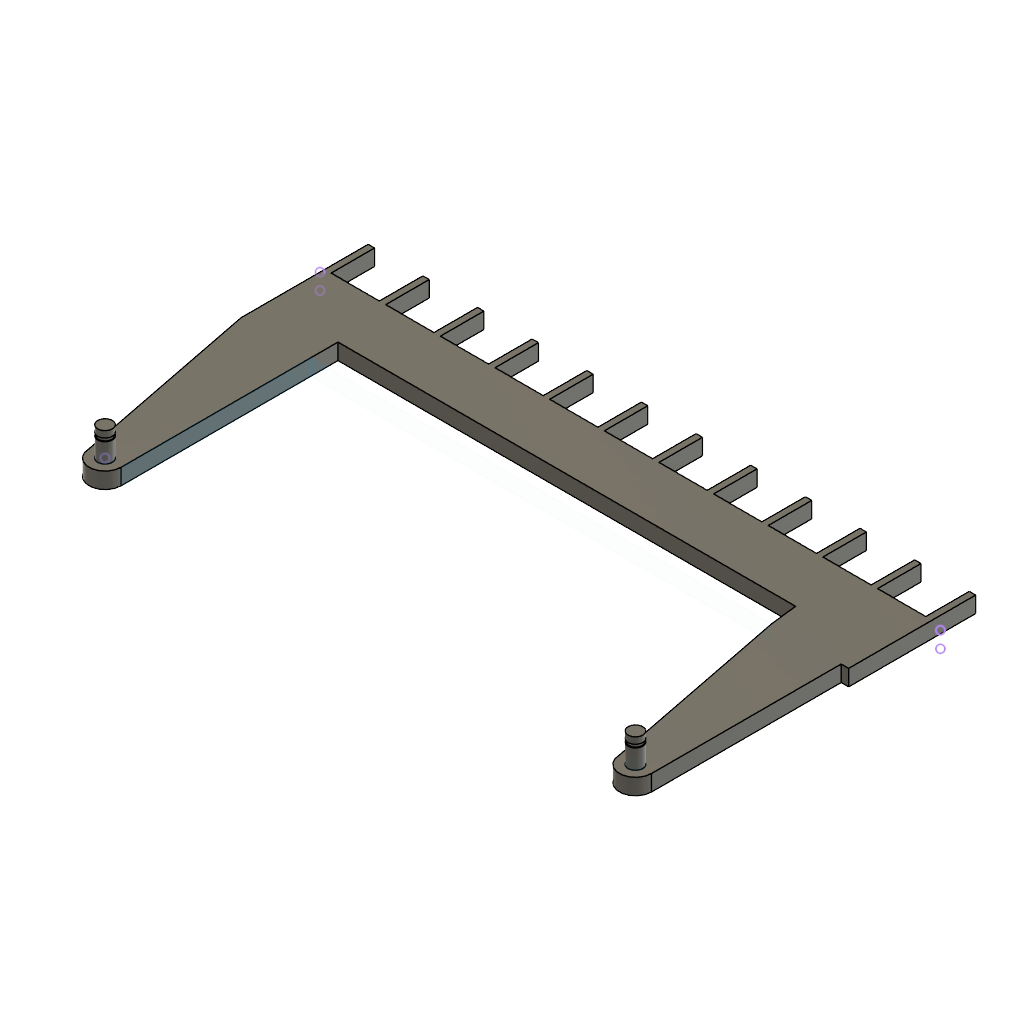
link 8 (Autodesk Fusion 360 design; units mm, degrees)
part number: 2026-11-18-20-14-19-061
Autodesk Fusion 360 part; units mm, degrees
note: some values were not read from the file. Set by a fixed rule: which face or edge a step refers to.
sketch "Sketch1" plane through (0, 0, 0) normal (0, 1, 0) x (1, 0, 0)
  line L0 (0, -5) -> (165, -5)
  arc A0 (165, -5) -> (165, 5) centre (165, 0) ccw
  line L1 (165, 5) -> (0, 5)
  arc A1 (0, 5) -> (0, -5) centre (0, 0) ccw
  line L2 (0, 0) -> (165, 0) construction
  circle A2 centre (0, 0) radius 2.5
  circle A3 centre (165, 0) radius 2.5
  circle A4 centre (0, 0) radius 5
  circle A5 centre (165, 0) radius 5
  line L3 (-16.6629, 74) -> (183.3371, 74)
  line L4 (183.3371, 74) -> (183.3371, 59)
  line L5 (183.3371, 59) -> (-16.6629, 59)
  line L6 (-16.6629, 59) -> (-16.6629, 74)
  line L7 (5, 0) -> (5, 59)
  line L8 (170, 0) -> (170, 59)
  line L9 (-5, 0) -> (-16.6629, 59)
  line L10 (160, 0) -> (148.3371, 59)
  dimension "d1" = 10
  dimension "d2" = 5
  dimension "d3" = 5
  dimension "d4" = 10
  dimension "d5" = 10
  dimension "d6" = 200
  dimension "d7" = 15
  constraint tangent L0 A0
  constraint tangent A0 L1
  constraint parallel L0 L1
  constraint tangent L1 A1
  constraint tangent L0 A1
  constraint horizontal L2
  constraint coincident A1.centre L2.start
  constraint concentric A1 A2
  constraint concentric A0 A3
  constraint concentric A0 A5
  constraint horizontal L3
  constraint vertical L4
  constraint horizontal L5
  constraint vertical L6
  constraint coincident A4 L7.start
  constraint coincident L2 L7.start
  constraint coincident L5 L7.end
  constraint perpendicular L5 L7
  constraint midpoint A0 L8.start
  constraint coincident L5 L8.end
  constraint tangent A5 L8
  constraint perpendicular L5 L8
  constraint midpoint A1 L9.start
  constraint coincident L2 L10.start
  constraint coincident A5 L10.start
  constraint coincident L5 L10.end
  constraint parallel L9 L10
  measures "d1" diameter of A0
  measures "d2" diameter of A2
  measures "d3" diameter of A3
  measures "d4" diameter of A4
  measures "d5" diameter of A5
  measures "d6" distance of L4.end L5.end
  measures "d7" distance of L3.start L5.end
extrude "Extrude1" add sketch "Sketch1" along normal blind 5 contours A1 A4 | A0 A5 | L1 A1 A4 L5 L7 L9 | L1 A4 L7 | A0 L1 A5 L5 L8 L10 | L1 A5 L10 | L3 L4 L5 L6 makes body 1
sketch "Sketch2" plane through (0, 0, 0) normal (0, -1, 0) x (1, 0, 0)
  circle A0 centre (165, 0) radius 2.5
  circle A1 centre (0, 0) radius 2.5
  arc A2 (170, 0) -> (160, 0) centre (165, 0) ccw
  line L0 (160, 0) -> (148.3371, -59)
  line L1 (148.3371, -59) -> (5, -59)
  line L2 (5, -59) -> (5, 0)
  arc A3 (5, 0) -> (-5, 0) centre (0, 0) ccw
  line L3 (-5, 0) -> (-16.6629, -59)
  line L4 (-16.6629, -59) -> (-16.6629, -74)
  line L5 (-16.6629, -74) -> (183.3371, -74)
  line L6 (183.3371, -74) -> (183.3371, -59)
  line L7 (183.3371, -59) -> (170, -59)
  line L8 (170, -59) -> (170, 0)
  circle A4 centre (0, 0) radius 2.5
  dimension "d85" = 15
  constraint concentric A1 A4
  measures "d85" distance of L1 L5
extrude "Extrude2" add sketch "Sketch2" against normal blind 13 contours A1 A4 bodies 1
sketch "Sketch3" plane through (5, 0, 0) normal (1, 0, 0) x (0, 0, -1)
  line L0 (0, 0) -> (59, 0)
  line L1 (59, 0) -> (59, 5)
  line L2 (59, 5) -> (0, 5)
  line L3 (0, 5) -> (0, 0)
sketch "Sketch4" plane through (5, 0, 0) normal (1, 0, 0) x (0, 0, -1)
extrude "Extrude3" cut 1 faces at (-0.7508, 13, 0.3616) along direction (0, -1, 0) blind 3 on bodies 1 bodies 1
sketch "Sketch5" plane through (0, 10, 0) normal (0, 1, 0) x (-1, 0, 0)
  circle A0 centre (0, 0) radius 2.5
  circle A1 centre (0, 0) radius 2.45
  dimension "d14" = 4.9
  constraint concentric A0 A1
  measures "d14" diameter of A1
extrude "Extrude4" add sketch "Sketch5" along normal blind 1 contours A1 bodies 1
sketch "Sketch6" plane through (0, 11, 0) normal (0, 1, 0) x (-1, 0, 0)
  circle A0 centre (0, 0) radius 2.45
  circle A1 centre (0, 0) radius 2.5
  dimension "d17" = 5
  constraint coincident A0.centre A1.centre
  measures "d17" diameter of A1
extrude "Extrude5" add sketch "Sketch6" along normal blind 1 separate body makes body 2
extrude "Extrude6" add 1 faces at (0.5987, 11, 0.5555) along direction (0, 1, 0) blind 1 on bodies 1 bodies 1 2
sketch "Sketch7" plane through (5, 0, 0) normal (1, 0, 0) x (0, 0, -1)
sketch "Sketch8" plane through (0, 0, -59) normal (0, 0, 1) x (1, 0, 0)
  line L0 (5, 0) -> (148.3371, 0)
  line L1 (148.3371, 0) -> (148.3371, 5)
  line L2 (148.3371, 5) -> (5, 5)
  line L3 (5, 5) -> (5, 0)
sketch "Sketch9" plane through (0, 5, 0) normal (0, 1, 0) x (-1, 0, 0)
  circle A0 centre (-165, 0) radius 2.5
  circle A1 centre (0, 0) radius 2.5
  arc A2 (-160, 0) -> (-170, 0) centre (-165, 0) ccw
  line L0 (-170, 0) -> (-170, -59)
  line L1 (-170, -59) -> (-183.3371, -59)
  line L2 (-183.3371, -59) -> (-183.3371, -74)
  line L3 (-183.3371, -74) -> (16.6629, -74)
  line L4 (16.6629, -74) -> (16.6629, -59)
  line L5 (16.6629, -59) -> (5, 0)
  arc A3 (5, 0) -> (-5, 0) centre (0, 0) ccw
  line L6 (-5, 0) -> (-5, -59)
  line L7 (-5, -59) -> (-148.3371, -59)
  line L8 (-148.3371, -59) -> (-160, 0)
  circle A4 centre (-165, 0) radius 2.5
  constraint concentric A0 A4
extrude "Extrude7" add sketch "Sketch9" along normal blind 5 separate body contours A0 A4 makes body 3
extrude "Extrude8" add 1 faces at (164.3891, 5, 0.5668) along direction (0, -1, 0) blind 5 on bodies 3 bodies 1 3
sketch "Sketch10" plane through (0, 10, 0) normal (0, 1, 0) x (-1, 0, 0)
sketch "Sketch11" plane through (0, 10, 0) normal (0, 1, 0) x (-1, 0, 0)
  circle A0 centre (-165, 0) radius 2.45
  dimension "d28" = 4.9
  measures "d28" diameter of A0
extrude "Extrude9" add sketch "Sketch11" along normal blind 1 bodies 1
sketch "Sketch12" plane through (0, 11, 0) normal (0, 1, 0) x (-1, 0, 0)
  circle A0 centre (-165, 0) radius 2.45
  circle A1 centre (-165, 0) radius 2.5
  dimension "d31" = 5
  constraint concentric A0 A1
  measures "d31" diameter of A1
extrude "Extrude10" add sketch "Sketch12" along normal blind 1 separate body makes body 4
extrude "Extrude11" add 1 faces at (164.8237, 11, 0.7602) along direction (0, 1, 0) blind 1 on bodies 1 bodies 1 4
sketch "Sketch13" plane through (0, 5, 0) normal (0, 1, 0) x (-1, 0, 0)
  circle A0 centre (-165, 0) radius 2.5
  circle A1 centre (0, 0) radius 2.5
  arc A2 (-160, 0) -> (-170, 0) centre (-165, 0) ccw
  line L0 (-170, 0) -> (-170, -59)
  line L1 (-170, -59) -> (-183.3371, -59)
  line L2 (-183.3371, -59) -> (-183.3371, -74)
  line L3 (-183.3371, -74) -> (16.6629, -74)
  line L4 (16.6629, -74) -> (16.6629, -59)
  line L5 (16.6629, -59) -> (5, 0)
  arc A3 (5, 0) -> (-5, 0) centre (0, 0) ccw
  line L6 (-5, 0) -> (-5, -59)
  line L7 (-5, -59) -> (-148.3371, -59)
  line L8 (-148.3371, -59) -> (-160, 0)
  line L9 (16.6629, -74) -> (6.0563, -63.3934)
  line L10 (16.6629, -74) -> (1.6629, -74) construction
  line L11 (6.0563, -63.3934) -> (-4.5503, -74)
  line L12 (-4.5503, -74) -> (-15.1569, -63.3934)
  line L13 (-15.1569, -63.3934) -> (-25.7635, -74)
  line L14 (-25.7635, -74) -> (-36.3701, -63.3934)
  line L15 (-36.3701, -63.3934) -> (-46.9767, -74)
  line L16 (-46.9767, -74) -> (-57.5833, -63.3934)
  line L17 (-57.5833, -63.3934) -> (-68.1899, -74)
  line L18 (-68.1899, -74) -> (-78.7965, -63.3934)
  line L19 (-78.7965, -63.3934) -> (-89.4031, -74)
  line L20 (-89.4031, -74) -> (-100.0097, -63.3934)
  line L21 (-100.0097, -63.3934) -> (-110.6163, -74)
  line L22 (-110.6163, -74) -> (-121.2229, -63.3934)
  line L23 (-121.2229, -63.3934) -> (-131.8295, -74)
  line L24 (-131.8295, -74) -> (-142.4361, -63.3934)
  line L25 (-142.4361, -63.3934) -> (-153.0427, -74)
  line L26 (-153.0427, -74) -> (-163.6493, -63.3934)
  line L27 (-163.6493, -63.3934) -> (-174.2559, -74)
  line L28 (-174.2559, -74) -> (-184.8625, -63.3934)
  dimension "d36" = 45
  dimension "d37" = 15
  dimension "d38" = 15
  dimension "d39" = 15
  dimension "d40" = 15
  dimension "d41" = 15
  dimension "d42" = 15
  dimension "d43" = 15
  dimension "d44" = 15
  dimension "d45" = 15
  dimension "d46" = 15
  dimension "d47" = 15
  dimension "d48" = 15
  constraint horizontal L10
  constraint coincident L3.end L4.start
  constraint coincident L3 L11.end
  constraint perpendicular L9 L11
  constraint perpendicular L11 L12
  constraint coincident L3 L13.end
  constraint perpendicular L12 L13
  constraint perpendicular L13 L14
  constraint coincident L3 L15.end
  constraint perpendicular L15 L16
  constraint perpendicular L16 L17
  constraint perpendicular L17 L18
  constraint perpendicular L18 L19
  constraint perpendicular L19 L20
  constraint coincident L3 L21.end
  constraint perpendicular L18 L21
  constraint perpendicular L21 L22
  constraint coincident L3 L23.end
  constraint perpendicular L22 L23
  constraint perpendicular L23 L24
  constraint perpendicular L22 L25
  constraint perpendicular L25 L26
  constraint perpendicular L26 L27
  constraint perpendicular L27 L28
  measures "d36" angle of L9 L10
  measures "d37" distance of L3.end L9.end
  measures "d38" distance of L13.end L14.end
  measures "d39" distance of L14.end L15.end
  measures "d40" distance of L16.end L17.end
  measures "d41" distance of L17.end L18.end
  measures "d42" distance of L18.end L19.end
  measures "d43" distance of L19.end L20.end
  measures "d44" distance of L21.end L22.end
  measures "d45" distance of L23.end L24.end
  measures "d46" distance of L24.end L25.end
  measures "d47" distance of L25.end L26.end
  measures "d48" distance of L26.end L27.end
extrude "Extrude12" cut sketch "Sketch13" against normal blind 20 contours L2 L3 L28 | L3 L26 L27 | L3 L24 L25 | L3 L9 L11 | L3 L22 L23 | L3 L12 L13 | L3 L20 L21 | L3 L14 L15 | L3 L18 L19 | L3 L16 L17 bodies 1
sketch "Sketch14" plane through (0, 10, 0) normal (0, 1, 0) x (-1, 0, 0)
sketch "Sketch15" plane through (0, 12, 0) normal (0, 1, 0) x (-1, 0, 0)
  circle A0 centre (0, 0) radius 2.5
  circle A1 centre (0, 0) radius 2.45
  dimension "d51" = 4.9
  constraint coincident A0.centre A1.centre
  measures "d51" diameter of A1
extrude "Extrude13" cut sketch "Sketch15" against normal blind 7 bodies 1
sketch "Sketch16" plane through (0, 12, 0) normal (0, 1, 0) x (-1, 0, 0)
  circle A0 centre (0, 0) radius 2.45
sketch "Sketch17" plane through (0, 10, 0) normal (0, 1, 0) x (-1, 0, 0)
sketch "Sketch18" plane through (0, 12, 0) normal (0, 1, 0) x (-1, 0, 0)
  circle A0 centre (-165, 0) radius 2.5
  circle A1 centre (-165, 0) radius 2.45
  dimension "d54" = 4.9
  constraint concentric A0 A1
  measures "d54" diameter of A1
extrude "Extrude14" cut sketch "Sketch18" against normal blind 7 bodies 1
extrude "Extrude15" cut sketch "Sketch16" against normal blind 6 bodies 1
sketch "Sketch19" plane through (0, 6, 0) normal (0, 1, 0) x (-1, 0, 0)
  circle A0 centre (0, 0) radius 2.45
  circle A1 centre (0, 0) radius 2.3
  dimension "d59" = 4.6
  constraint concentric A0 A1
  measures "d59" diameter of A1
extrude "Extrude16" cut sketch "Sketch19" against normal blind 1 bodies 1
extrude "Extrude17" add 1 faces at (-0.6867, 6, 1.0676) along direction (0, 1, 0) blind 5 on bodies 1 bodies 1
sketch "Sketch20" plane through (0, 11, 0) normal (0, 1, 0) x (-1, 0, 0)
  circle A0 centre (0, 0) radius 2.3
  circle A1 centre (0, 0) radius 2
  dimension "d64" = 4
  constraint coincident A0.centre A1.centre
  measures "d64" diameter of A1
extrude "Extrude18" add sketch "Sketch20" along normal blind 1 contours A1 bodies 1
sketch "Sketch21" plane through (0, 12, 0) normal (0, 1, 0) x (-1, 0, 0)
  circle A0 centre (0, 0) radius 2
  circle A1 centre (0, 0) radius 2.3
  dimension "d67" = 4.6
  constraint concentric A0 A1
  measures "d67" diameter of A1
extrude "Extrude19" add sketch "Sketch21" along normal blind 2 contours A0 | A1 bodies 1
extrude "Extrude20" cut 1 faces at (164.8237, 12, 0.7602) along direction (0, -1, 0) blind 5 on bodies 1 bodies 1
sketch "Sketch22" plane through (0, 7, 0) normal (0, 1, 0) x (-1, 0, 0)
  circle A0 centre (-165, 0) radius 2.45
  circle A1 centre (-165, 0) radius 2.3
  dimension "d72" = 4.6
  constraint concentric A0 A1
  measures "d72" diameter of A1
extrude "Extrude21" cut sketch "Sketch22" against normal blind 1 bodies 1
extrude "Extrude22" cut 1 faces at (162.6091, 6, -0.1217) along direction (0, -1, 0) blind 1 on bodies 1 bodies 1
extrude "Extrude23" add 1 faces at (165.3833, 7, -1.3292) along direction (0, 1, 0) blind 4 on bodies 1 bodies 1
sketch "Sketch23" plane through (0, 11, 0) normal (0, 1, 0) x (-1, 0, 0)
  circle A0 centre (-165, 0) radius 2.3
  circle A1 centre (-165, 0) radius 2
  dimension "d79" = 4
  constraint concentric A0 A1
  measures "d79" diameter of A1
extrude "Extrude24" add sketch "Sketch23" along normal blind 1 contours A1 bodies 1
sketch "Sketch24" plane through (0, 12, 0) normal (0, 1, 0) x (-1, 0, 0)
  circle A0 centre (-165, 0) radius 2
  circle A1 centre (-165, 0) radius 2.3
  dimension "d82" = 4.6
  constraint concentric A0 A1
  measures "d82" diameter of A1
extrude "Extrude25" add sketch "Sketch24" along normal blind 2 contours A0 | A1 bodies 1
sketch "Sketch25" plane through (0, 0, 0) normal (0, -1, 0) x (1, 0, 0)
  line L0 (-16.6629, -74) -> (-6.0563, -63.3934)
  line L1 (-6.0563, -63.3934) -> (4.5503, -74)
  line L2 (4.5503, -74) -> (15.1569, -63.3934)
  line L3 (15.1569, -63.3934) -> (25.7635, -74)
  line L4 (25.7635, -74) -> (36.3701, -63.3934)
  line L5 (36.3701, -63.3934) -> (46.9767, -74)
  line L6 (46.9767, -74) -> (57.5833, -63.3934)
  line L7 (57.5833, -63.3934) -> (68.1899, -74)
  line L8 (68.1899, -74) -> (78.7965, -63.3934)
  line L9 (78.7965, -63.3934) -> (89.4031, -74)
  line L10 (89.4031, -74) -> (100.0097, -63.3934)
  line L11 (100.0097, -63.3934) -> (110.6163, -74)
  line L12 (110.6163, -74) -> (121.2229, -63.3934)
  line L13 (121.2229, -63.3934) -> (131.8295, -74)
  line L14 (131.8295, -74) -> (142.4361, -63.3934)
  line L15 (142.4361, -63.3934) -> (153.0427, -74)
  line L16 (153.0427, -74) -> (163.6493, -63.3934)
  line L17 (163.6493, -63.3934) -> (174.2559, -74)
  line L18 (174.2559, -74) -> (183.3371, -64.9188)
  line L19 (183.3371, -64.9188) -> (183.3371, -59)
  line L20 (183.3371, -59) -> (170, -59)
  line L21 (170, -59) -> (170, 0)
  arc A0 (170, 0) -> (160, 0) centre (165, 0) ccw
  line L22 (160, 0) -> (148.3371, -59)
  line L23 (148.3371, -59) -> (5, -59)
  line L24 (5, -59) -> (5, 0)
  arc A1 (5, 0) -> (-5, 0) centre (0, 0) ccw
  line L25 (-5, 0) -> (-16.6629, -59)
  line L26 (-16.6629, -59) -> (-16.6629, -74)
  line L27 (174.2559, -74) -> (153.0427, -74)
  line L28 (131.8295, -74) -> (153.0427, -74)
  line L29 (131.8295, -74) -> (110.6163, -74)
  line L30 (89.4031, -74) -> (110.6163, -74)
  line L31 (89.4031, -74) -> (68.1899, -74)
  line L32 (68.1899, -74) -> (46.9767, -74)
  line L33 (46.9767, -74) -> (25.7635, -74)
  line L34 (25.7635, -74) -> (4.5503, -74)
  line L35 (-16.6629, -74) -> (4.5503, -74)
  constraint coincident L17.end L18.start
  constraint coincident L15.end L16.start
  constraint coincident L13.end L14.start
  constraint coincident L11.end L12.start
  constraint coincident L9.end L10.start
  constraint coincident L7.end L8.start
  constraint coincident L5.end L6.start
  constraint coincident L3.end L4.start
  constraint coincident L1.end L2.start
  constraint coincident L0.start L26.end
extrude "Extrude26" add sketch "Sketch25" against normal blind 5 contours L0 L1 L35 | L2 L3 L34 | L4 L5 L33 | L6 L7 L32 | L8 L9 L31 | L10 L11 L30 | L12 L13 L29 | L14 L15 L28 | L16 L17 L27 bodies 1
sketch "Sketch26" plane through (0, 5, 0) normal (0, 1, 0) x (-1, 0, 0)
  circle A0 centre (-165, 0) radius 2.3
  circle A1 centre (0, 0) radius 2.3
  line L0 (16.6629, -74) -> (16.6629, -59)
  line L1 (16.6629, -59) -> (5, 0)
  arc A2 (5, 0) -> (-5, 0) centre (0, 0) ccw
  line L2 (-5, 0) -> (-5, -59)
  line L3 (-5, -59) -> (-148.3371, -59)
  line L4 (-148.3371, -59) -> (-160, 0)
  arc A3 (-160, 0) -> (-170, 0) centre (-165, 0) ccw
  line L5 (-170, 0) -> (-170, -59)
  line L6 (-170, -59) -> (-183.3371, -59)
  line L7 (-183.3371, -59) -> (-183.3371, -64.9188)
  line L8 (-183.3371, -64.9188) -> (-174.2559, -74)
  line L9 (-174.2559, -74) -> (16.6629, -74)
  line L10 (-5, -59) -> (-5, -67.4629)
  line L11 (-5, -67.4629) -> (-147.358, -67.4629)
  line L12 (-147.358, -67.4629) -> (-148.3371, -59)
  constraint coincident L2.end L3.start
  constraint perpendicular L3 L10
  constraint perpendicular L10 L11
  constraint coincident L3.end L4.start
extrude "Extrude27" cut sketch "Sketch26" against normal blind 30 contours L3 L10 L11 L12 bodies 1
extrude "Extrude28" add 9 faces at (138.9005, 1.6667, -74) (167.1848, 1.6667, -74) (18.6924, 1.6667, -74) (39.9056, 1.6667, -74) (61.1188, 1.6667, -74) (82.332, 1.6667, -74) (96.4741, 3.3333, -74) (124.7584, 1.6667, -74) (-9.5919, 1.6667, -74) along direction (0, 0, -1) blind 30 on bodies 1 bodies 1
extrude "Extrude29" cut 1 faces at (46.9767, 1.6667, -104) along direction (0, 0, 1) blind 20 on bodies 1 bodies 1
sketch "Sketch27" plane through (0, 5, 0) normal (0, 1, 0) x (-1, 0, 0)
  line L0 (-174.2559, -84) -> (16.6629, -84)
  line L1 (16.6629, -84) -> (16.6629, -59)
  line L2 (16.6629, -59) -> (5, 0)
  arc A0 (5, 0) -> (-5, 0) centre (0, 0) ccw
  line L3 (-5, 0) -> (-5, -67.4629)
  line L4 (-5, -67.4629) -> (-147.358, -67.4629)
  line L5 (-147.358, -67.4629) -> (-148.3371, -59)
  line L6 (-148.3371, -59) -> (-160, 0)
  arc A1 (-160, 0) -> (-170, 0) centre (-165, 0) ccw
  line L7 (-170, 0) -> (-170, -59)
  line L8 (-170, -59) -> (-183.3371, -59)
  line L9 (-183.3371, -59) -> (-183.3371, -64.9188)
  line L10 (-183.3371, -64.9188) -> (-174.2559, -74)
  line L11 (-174.2559, -74) -> (-174.2559, -84)
  circle A2 centre (0, 0) radius 2.3
  circle A3 centre (-165, 0) radius 2.3
  line L12 (16.6629, -84) -> (6.0563, -73.3934)
  line L13 (16.6629, -84) -> (1.6629, -84) construction
  line L14 (6.0563, -73.3934) -> (-4.5503, -84)
  line L15 (-4.5503, -84) -> (-15.1569, -73.3934)
  line L16 (-15.1569, -73.3934) -> (-25.7635, -84)
  line L17 (-25.7635, -84) -> (-36.3701, -73.3934)
  line L18 (-36.3701, -73.3934) -> (-46.9767, -84)
  line L19 (-46.9767, -84) -> (-57.5833, -73.3934)
  line L20 (-57.5833, -73.3934) -> (-68.1899, -84)
  line L21 (-68.1899, -84) -> (-78.7965, -73.3934)
  line L22 (-78.7965, -73.3934) -> (-89.4031, -84)
  line L23 (-88.6327, -84) -> (-99.2393, -73.3934)
  line L24 (-99.2393, -73.3934) -> (-109.8459, -84)
  line L25 (-109.8459, -84) -> (-120.4525, -73.3934)
  line L26 (-120.4525, -73.3934) -> (-131.0591, -84)
  line L27 (-131.0591, -84) -> (-141.6657, -73.3934)
  line L28 (-141.6657, -73.3934) -> (-152.2723, -84)
  line L29 (-152.2723, -84) -> (-162.8789, -73.3934)
  line L30 (-162.8789, -73.3934) -> (-174.2559, -84)
  dimension "d94" = 45
  dimension "d95" = 15
  dimension "d96" = 15
  dimension "d97" = 15
  dimension "d98" = 15
  dimension "d99" = 15
  dimension "d100" = 15
  dimension "d101" = 15
  dimension "d102" = 15
  dimension "d103" = 15
  dimension "d104" = 15
  dimension "d105" = 15
  dimension "d106" = 15
  constraint horizontal L13
  constraint coincident L0.end L1.start
  constraint coincident L0 L14.end
  constraint perpendicular L14 L15
  constraint coincident L0 L16.end
  constraint perpendicular L16 L17
  constraint coincident L0 L18.end
  constraint perpendicular L17 L18
  constraint perpendicular L18 L19
  constraint coincident L0 L20.end
  constraint perpendicular L19 L20
  constraint perpendicular L20 L21
  constraint coincident L0 L22.end
  constraint perpendicular L21 L22
  constraint coincident L0 L23.start
  constraint perpendicular L22 L23
  constraint coincident L0 L24.end
  constraint perpendicular L21 L24
  constraint perpendicular L24 L25
  constraint perpendicular L25 L26
  constraint perpendicular L26 L27
  constraint coincident L0 L28.end
  constraint perpendicular L27 L28
  constraint perpendicular L28 L29
  constraint coincident L0.start L11.end
  measures "d94" angle of L12 L13
  measures "d95" distance of L0.end L12.end
  measures "d96" distance of L12.end L14.end
  measures "d97" distance of L14.end L15.end
  measures "d98" distance of L15.end L16.end
  measures "d99" distance of L16.end L17.end
  measures "d100" distance of L18.end L19.end
  measures "d101" distance of L21.end L22.end
  measures "d102" distance of L23.start L23.end
  measures "d103" distance of L24.end L25.end
  measures "d104" distance of L25.end L26.end
  measures "d105" distance of L26.end L27.end
  measures "d106" distance of L28.end L29.end
extrude "Extrude30" cut sketch "Sketch27" against normal blind 30 contours L0 L29 L30 | L0 L27 L28 | L0 L25 L26 | L0 L22 L23 L24 | L0 L21 L22 L23 | L0 L19 L20 | L0 L17 L18 | L0 L15 L16 | L0 L12 L14 bodies 1
sketch "Sketch28" plane through (0, 5, 0) normal (0, 1, 0) x (-1, 0, 0)
  circle A0 centre (-165, 0) radius 2.3
  circle A1 centre (0, 0) radius 2.3
sketch "Sketch29" plane through (0, 5, 0) normal (0, 1, 0) x (-1, 0, 0)
sketch "Sketch30" plane through (0, 5, 0) normal (0, 1, 0) x (-1, 0, 0)
sketch "Sketch31" plane through (0, 5, 0) normal (0, 1, 0) x (-1, 0, 0)
sketch "Sketch32" plane through (0, 5, 0) normal (0, 1, 0) x (-1, 0, 0)
sketch "Sketch33" plane through (-16.6629, 0, 0) normal (-1, 0, 0) x (0, 0, 1)
sketch "Sketch34" plane through (-16.6629, 0, 0) normal (-1, 0, 0) x (0, 0, 1)
sketch "Sketch35" plane through (0, 5, 0) normal (0, 1, 0) x (-1, 0, 0)
sketch "Sketch36" plane through (0, 5, 0) normal (0, 1, 0) x (-1, 0, 0)
sketch "Sketch37" plane through (0, 5, 0) normal (0, 1, 0) x (-1, 0, 0)
extrude "Extrude31" cut 1 faces at (174.2559, 3.3333, -77.3333) along direction (-1, 0, 0) blind 200 on bodies 1 bodies 1
extrude "Extrude32" cut 1 faces at (134.3924, 3.3333, -74) along direction (0, 0, 1) blind 3 on bodies 1 bodies 1
extrude "Extrude33" cut 1 faces at (121.0591, 3.3333, -72) along direction (-1, 0, 0) blind 144 on bodies 1 bodies 1
extrude "Extrude34" cut 1 faces at (141.0591, 1.6667, -73) along direction (1, 0, 0) blind 58.5 on bodies 1 bodies 1
extrude "Extrude35" cut 1 faces at (112.6163, 3.3333, -71) along direction (0, 0, 1) blind 3 on bodies 1 bodies 1
extrude "Extrude36" add 1 faces at (112.6163, 3.3333, -68) along direction (0, 0, -1) blind 15.537 on bodies 1 bodies 1
extrude "Extrude37" cut 1 faces at (183.3371, 1.6667, -62.9459) along direction (-1, 0, 0) blind 6 on bodies 1 bodies 1
extrude "Extrude38" cut 1 faces at (177.3371, 1.6667, -62.9459) along direction (-1, 0, 0) blind 1 on bodies 1 bodies 1
extrude "Extrude39" cut 1 faces at (181.0037, 3.3333, -64.9188) along direction (0, 0, -1) blind 20 on bodies 1 bodies 1
sketch "Sketch38" plane through (0, 0, -83.537) normal (0, 0, -1) x (-1, 0, 0)
  line L0 (-176.3371, 5) -> (-176.3371, 0)
  line L1 (16.6629, 0) -> (16.6629, 5)
sketch "Sketch39" plane through (0, 5, 0) normal (0, 1, 0) x (-1, 0, 0)
  line L0 (-176.3371, -59) -> (-176.3371, -83.537)
  line L1 (-176.3371, -83.537) -> (16.6629, -83.537)
  line L2 (16.6629, -83.537) -> (16.6629, -59)
  line L3 (16.6629, -59) -> (5, 0)
  arc A0 (5, 0) -> (-5, 0) centre (0, 0) ccw
  line L4 (-5, 0) -> (-5, -67.4629)
  line L5 (-5, -67.4629) -> (-147.358, -67.4629)
  line L6 (-147.358, -67.4629) -> (-148.3371, -59)
  line L7 (-148.3371, -59) -> (-160, 0)
  arc A1 (-160, 0) -> (-170, 0) centre (-165, 0) ccw
  line L8 (-170, 0) -> (-170, -59)
  line L9 (-170, -59) -> (-176.3371, -59)
  circle A2 centre (0, 0) radius 2.3
  circle A3 centre (-165, 0) radius 2.3
  line L10 (16.6629, -83.537) -> (14.6629, -83.537)
  line L11 (14.6629, -83.537) -> (14.6629, -70)
  line L12 (14.6629, -70) -> (-0.3371, -70)
  line L13 (-0.3371, -70) -> (-0.3371, -83.537)
  line L14 (-0.3371, -83.537) -> (-2.3371, -83.537)
  line L15 (-2.3371, -83.537) -> (-2.3371, -70)
  line L16 (-2.3371, -70) -> (-17.3371, -70)
  line L17 (-17.3371, -70) -> (-17.3371, -83.537)
  line L18 (-17.3371, -83.537) -> (-19.3371, -83.537)
  line L19 (-19.3371, -83.537) -> (-19.3371, -70)
  line L20 (-19.3371, -70) -> (-34.3371, -70)
  line L21 (-34.3371, -70) -> (-34.3371, -83.537)
  line L22 (-34.3371, -83.537) -> (-36.3371, -83.537)
  line L23 (-36.3371, -83.537) -> (-36.3371, -70)
  line L24 (-36.3371, -70) -> (-51.3371, -70)
  line L25 (-51.3371, -70) -> (-51.3371, -83.537)
  line L26 (-51.3371, -83.537) -> (-53.3371, -83.537)
  line L27 (-53.3371, -83.537) -> (-53.3371, -70)
  line L28 (-53.3371, -70) -> (-68.3371, -70)
  line L29 (-68.3371, -70) -> (-68.3371, -83.537)
  line L30 (-68.3371, -83.537) -> (-70.3371, -83.537)
  line L31 (-70.3371, -83.537) -> (-70.3371, -70)
  line L32 (-70.3371, -70) -> (-85.3371, -70)
  line L33 (-85.3371, -70) -> (-85.3371, -83.537)
  line L34 (-85.3371, -83.537) -> (-87.3371, -83.537)
  line L35 (-87.3371, -83.537) -> (-87.3371, -70)
  line L36 (-87.3371, -70) -> (-102.3371, -70)
  line L37 (-102.3371, -70) -> (-102.3371, -83.537)
  line L38 (-102.3371, -83.537) -> (-104.3371, -83.537)
  line L39 (-104.3371, -83.537) -> (-104.3371, -70)
  line L40 (-104.3371, -70) -> (-119.3371, -70)
  line L41 (-119.3371, -70) -> (-119.3371, -83.537)
  line L42 (-119.3371, -83.537) -> (-121.3371, -83.537)
  line L43 (-121.3371, -83.537) -> (-121.3371, -70)
  line L44 (-121.3371, -70) -> (-136.3371, -70)
  line L45 (-136.3371, -70) -> (-136.3371, -83.537)
  line L46 (-136.3371, -83.537) -> (-138.3371, -83.537)
  line L47 (-138.3371, -83.537) -> (-138.3371, -70)
  line L48 (-138.3371, -70) -> (-153.3371, -70)
  line L49 (-153.3371, -70) -> (-153.3371, -83.537)
  line L50 (-153.3371, -83.537) -> (-155.3371, -83.537)
  line L51 (-155.3371, -83.537) -> (-155.3371, -70)
  line L52 (-155.3371, -70) -> (-170.3371, -70)
  line L53 (-170.3371, -70) -> (-170.3371, -83.537)
  line L54 (-170.3371, -83.537) -> (-172.3371, -83.537)
  line L55 (-172.3371, -83.537) -> (-172.3371, -70)
  line L56 (-172.3371, -70) -> (-176.3371, -70)
  dimension "d128" = 2
  dimension "d129" = 15
  dimension "d130" = 2
  dimension "d131" = 15
  dimension "d132" = 2
  dimension "d133" = 15
  dimension "d134" = 2
  dimension "d135" = 15
  dimension "d136" = 2
  dimension "d137" = 15
  dimension "d138" = 2
  dimension "d139" = 15
  dimension "d140" = 2
  dimension "d141" = 15
  dimension "d142" = 2
  dimension "d143" = 15
  dimension "d144" = 2
  dimension "d145" = 15
  dimension "d146" = 2
  dimension "d147" = 15
  dimension "d148" = 2
  dimension "d149" = 15
  dimension "d150" = 2
  constraint coincident L1.end L2.start
  constraint perpendicular L2 L10
  constraint perpendicular L10 L11
  constraint perpendicular L11 L12
  constraint coincident L1 L13.end
  constraint perpendicular L1 L13
  constraint perpendicular L13 L14
  constraint perpendicular L1 L15
  constraint perpendicular L15 L16
  constraint coincident L1 L17.end
  constraint perpendicular L1 L17
  constraint coincident L1 L18.end
  constraint perpendicular L18 L19
  constraint perpendicular L19 L20
  constraint coincident L1 L21.end
  constraint perpendicular L1 L21
  constraint perpendicular L21 L22
  constraint perpendicular L1 L23
  constraint perpendicular L23 L24
  constraint coincident L1 L25.end
  constraint perpendicular L1 L25
  constraint perpendicular L25 L26
  constraint perpendicular L26 L27
  constraint perpendicular L25 L28
  constraint coincident L1 L29.end
  constraint perpendicular L1 L29
  constraint perpendicular L29 L30
  constraint perpendicular L30 L31
  constraint perpendicular L31 L32
  constraint coincident L1 L33.end
  constraint perpendicular L1 L33
  constraint perpendicular L27 L34
  constraint perpendicular L34 L35
  constraint perpendicular L35 L36
  constraint coincident L1 L37.end
  constraint perpendicular L1 L37
  constraint perpendicular L37 L38
  constraint perpendicular L38 L39
  constraint perpendicular L39 L40
  constraint coincident L1 L41.end
  constraint perpendicular L1 L41
  constraint perpendicular L41 L42
  constraint perpendicular L42 L43
  constraint perpendicular L43 L44
  constraint coincident L1 L45.end
  constraint perpendicular L1 L45
  constraint perpendicular L45 L46
  constraint perpendicular L46 L47
  constraint perpendicular L47 L48
  constraint coincident L1 L49.end
  constraint perpendicular L1 L49
  constraint perpendicular L49 L50
  constraint perpendicular L50 L51
  constraint perpendicular L51 L52
  constraint coincident L1 L53.end
  constraint perpendicular L1 L53
  constraint perpendicular L53 L54
  constraint perpendicular L54 L55
  constraint coincident L0 L56.end
  constraint perpendicular L0 L56
  measures "d128" distance of L1.end L10.end
  measures "d129" distance of L11.end L12.end
  measures "d130" distance of L13.end L14.end
  measures "d131" distance of L15.end L16.end
  measures "d132" distance of L17.end L18.end
  measures "d133" distance of L19.end L20.end
  measures "d134" distance of L21.end L22.end
  measures "d135" distance of L23.end L24.end
  measures "d136" distance of L25.end L26.end
  measures "d137" distance of L27.end L28.end
  measures "d138" distance of L29.end L30.end
  measures "d139" distance of L31.end L32.end
  measures "d140" distance of L33.end L34.end
  measures "d141" distance of L35.end L36.end
  measures "d142" distance of L37.end L38.end
  measures "d143" distance of L39.end L40.end
  measures "d144" distance of L41.end L42.end
  measures "d145" distance of L43.end L44.end
  measures "d146" distance of L45.end L46.end
  measures "d147" distance of L47.end L48.end
  measures "d148" distance of L49.end L50.end
  measures "d149" distance of L51.end L52.end
  measures "d150" distance of L53.end L54.end
extrude "Extrude40" cut sketch "Sketch39" against normal blind 17 contours L0 L1 L55 L56 | L1 L51 L52 L53 | L1 L47 L48 L49 | L1 L43 L44 L45 | L1 L39 L40 L41 | L1 L11 L12 L13 | L1 L35 L36 L37 | L1 L15 L16 L17 | L1 L31 L32 L33 | L1 L19 L20 L21 | L1 L27 L28 L29 | L1 L23 L24 L25 bodies 1
extrude "Extrude41" cut 1 faces at (175.0037, 1.6667, -70) along direction (0, 0, 1) blind 34 on bodies 1 bodies 1
extrude "Extrude42" add 11 faces at (-9.6629, 3.3333, -70) (7.3371, 3.3333, -70) (24.3371, 3.3333, -70) (41.3371, 3.3333, -70) (58.3371, 3.3333, -70) (75.3371, 3.3333, -70) (92.3371, 3.3333, -70) (109.3371, 3.3333, -70) (126.3371, 3.3333, -70) (143.3371, 3.3333, -70) (160.3371, 1.6667, -70) along direction (0, 0, -1) blind 15 on bodies 1 bodies 1
extrude "Extrude43" add 12 faces at (171.0037, 1.6667, -83.537) (154.0037, 1.6667, -83.537) (137.0037, 1.6667, -83.537) (120.0037, 1.6667, -83.537) (103.0037, 1.6667, -83.537) (86.0037, 1.6667, -83.537) (69.0037, 1.6667, -83.537) (52.0037, 1.6667, -83.537) (35.0037, 1.6667, -83.537) (18.0037, 1.6667, -83.537) (1.0037, 1.6667, -83.537) (-15.3296, 1.6667, -83.537) along direction (0, 0, -1) blind 15 on bodies 1 bodies 1
